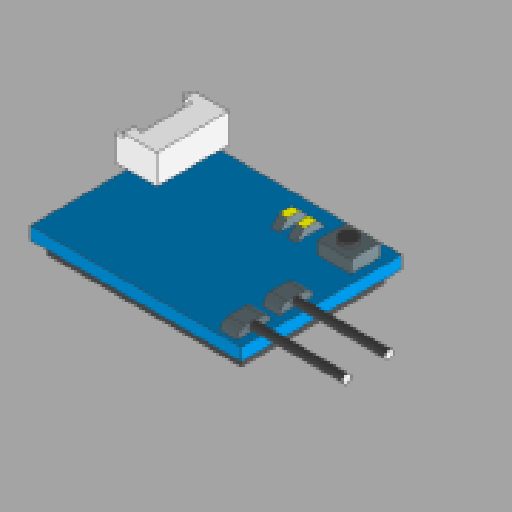
# Autodesk Inventor part: FrSky_XSR_receiver
Saved by Autodesk Inventor 2025 (Build 290162000, 162)
## iProperties
Created: 2024-11-10
Part Number: FrSky_XSR_receiver
Material: 일반
Document SubType Name: Modeling
Designer: OSB
Density: 1 g/cm^3
Appearance: 기본값
Author: OSB
Autodesk Inventor part; units mm, degrees
ref_plane "YZ Plane" through (0, 0, 0) normal (1, 0, 0) x (0, 1, 0)
ref_plane "XZ Plane" through (0, 0, 0) normal (0, 1, 0) x (-1, 0, 0)
ref_plane "XY Plane" through (0, 0, 0) normal (0, 0, 1) x (1, 0, 0)
sketch "스케치1" plane through (0, 0, 0) normal (0, 0, 1) x (1, 0, 0)
  line L0 (0, 0) -> (-19, 0)
  line L1 (-19, 0) -> (-19, 25)
  line L2 (-19, 25) -> (0, 25)
  line L3 (0, 25) -> (0, 0)
  line L4 (-11.5, 3.5) -> (-20, 3.5)
  line L5 (-20, 3.5) -> (-20, -1.5)
  line L6 (-20, -1.5) -> (-11.5, -1.5)
  line L7 (-11.5, -1.5) -> (-11.5, 3.5)
  line L8 (-2, 22) -> (-2, 35) construction
  line L9 (-3, 22) -> (-3, 35) construction
  line L10 (-7, 22) -> (-7, 35) construction
  line L11 (-8, 22) -> (-8, 35) construction
  line L12 (-17.5, 14) -> (-14, 14) construction
  line L13 (-14, 14) -> (-14, 18) construction
  line L14 (-14, 18) -> (-17.5, 18) construction
  line L15 (-17.5, 18) -> (-17.5, 14) construction
  line L16 (-17.5, 20) -> (-14, 20)
  line L17 (-14, 20) -> (-14, 24)
  line L18 (-14, 24) -> (-17.5, 24)
  line L19 (-17.5, 24) -> (-17.5, 20)
  line L20 (-9.5, 22) -> (-5.5, 22)
  line L21 (-5.5, 22) -> (-5.5, 24)
  line L22 (-5.5, 24) -> (-9.5, 24)
  line L23 (-9.5, 24) -> (-9.5, 22)
  line L24 (-4.5, 22) -> (-0.5, 22)
  line L25 (-0.5, 22) -> (-0.5, 24)
  line L26 (-0.5, 24) -> (-4.5, 24)
  line L27 (-4.5, 24) -> (-4.5, 22)
  line L28 (-18, 1) -> (-1, 1)
  line L29 (-1, 1) -> (-1, 24)
  line L30 (-1, 24) -> (-18, 24)
  line L31 (-18, 24) -> (-18, 1)
  line L32 (-17.5, 14.5) -> (-14, 14.5)
  line L33 (-14, 14.5) -> (-14, 15.5)
  line L34 (-14, 15.5) -> (-17.5, 15.5)
  line L35 (-17.5, 15.5) -> (-17.5, 14.5)
  line L36 (-17.5, 16.5) -> (-14, 16.5)
  line L37 (-14, 16.5) -> (-14, 17.5)
  line L38 (-14, 17.5) -> (-17.5, 17.5)
  line L39 (-17.5, 17.5) -> (-17.5, 16.5)
  point P0 (-2.5, 24)
  point P1 (-7.5, 24)
  point P2 (-1, 22)
  dimension "d0" = 19
  dimension "d1" = 25
  dimension "d2" = 11.5
  dimension "d3" = 8.5
  dimension "d4" = 5
  dimension "d5" = 1.5
  dimension "d6" = 2
  dimension "d8" = 1
  dimension "d9" = 7
  dimension "d10" = 1
  dimension "d11" = 7
  dimension "d12" = 4
  dimension "d13" = 3.5
  dimension "d14" = 1.5
  dimension "d15" = 3.5
  dimension "d16" = 1.5
  dimension "d17" = 4
  dimension "d18" = 1
  dimension "d20" = 3
  dimension "d21" = 2
  dimension "d22" = 4
  dimension "d23" = 4
  dimension "d24" = 0.5
  dimension "d25" = 0.5
  dimension "d26" = 10
  dimension "d29" = 1
  dimension "d32" = 1
  dimension "d33" = 1
  dimension "d34" = 1
  dimension "d35" = 0.5
  constraints: 80 end point, 18 parallel, 9 perpendicular, 8 horizontal, 8 point on line, 5 horizontal alignment, 4 vertical, 2 midpoint, 3 other
  measures "d0" distance of L1.end L2.end
  measures "d1" distance of L0.end L1.end
  measures "d2" distance between parallel lines of L3 L7
  measures "d3" distance of L5.end L6.end
  measures "d4" distance of L4.end L5.end
  measures "d5" distance between parallel lines of L6 L0
  measures "d6" distance between parallel lines of L3 L8
  measures "d8" distance between parallel lines of L8 L9
  measures "d9" distance between parallel lines of L10 L3
  measures "d10" distance between parallel lines of L11 L10
  measures "d11" distance between parallel lines of L2 L14
  measures "d12" distance between parallel lines of L14 L12
  measures "d13" distance between parallel lines of L13 L15
  measures "d14" distance between parallel lines of L1 L15
  measures "d15" distance of L17.end L18.end
  measures "d16" distance between parallel lines of L1 L19
  measures "d17" distance of L18.end L16.start
  measures "d18" distance between parallel lines of L2 L18
  measures "d20" distance between parallel lines of L2 L24
  measures "d21" distance of L24.end L25.end
  measures "d22" distance of L20.start L20.end
  measures "d23" distance of L24.start L24.end
  measures "d24" distance from line of point (-2.5, 24) L8
  measures "d25" distance from line of point (-7.5, 24) L10
  measures "d26" distance from line of L8.end L2
  measures "d29" distance between parallel lines of L0 L28
  measures "d32" distance of L32.end L33.end
  measures "d33" distance of L36.end L37.end
  measures "d34" distance between parallel lines of L34 L36
  measures "d35" distance between parallel lines of L12 L32
extrude "돌출1" add sketch "스케치1" along normal blind 1.5 contours L0 L7 L28 L29 L24 L25 L26 L30 L22 L18 L31 L4 L1 L2 L3 | L0 L1 L4 L31 L28 L7 | L28 L31 L4 L7 | L7 L4 L31 L30 L19 L16 L17 L23 L20 L21 L27 L24 L29 L28 | L29 L26 L25 L24 | L24 L27 L26 L29 | L18 L17 L16 L19 | L21 L20 L23 L22 | L35 L34 L33 L32 | L39 L38 L37 L36
extrude "돌출2" add sketch "스케치1" against normal blind 1.5 contours L28 L31 L4 L7 | L7 L4 L31 L30 L19 L16 L17 L23 L20 L21 L27 L24 L29 L28 | L24 L27 L26 L29 | L18 L17 L16 L19 | L21 L20 L23 L22 | L35 L34 L33 L32 | L39 L38 L37 L36
extrude "돌출3" add sketch "스케치1" along normal blind 1 from surface at 1.5 contours L29 L26 L25 L24 | L24 L27 L26 L29 | L21 L20 L23 L22 | L35 L34 L33 L32 | L39 L38 L37 L36
extrude "돌출4" add sketch "스케치1" along normal blind 2 from surface at 1.5 contours L18 L17 L16 L19
extrude "돌출5" add sketch "스케치1" along normal blind 3.5 from surface at 1.5 contours L7 L6 L5 L4 L1 L0 | L0 L1 L4 L31 L28 L7 | L28 L31 L4 L7
sketch "스케치2" plane through (-17.5, 20, 3.5) normal (0, 0, 1) x (1, 0, 0)
  line L0 (3.5, 0) -> (0, 0) projected
  line L1 (3.5, 4) -> (3.5, 0) projected
  line L2 (0, 4) -> (3.5, 4) projected
  line L3 (0, 0) -> (0, 4) projected
  circle A0 centre (1.75, 2) radius 1
  point P0 (17.5, -20)
  point P1 (0, 2)
  point P2 (1.75, 4)
  dimension "d42" = 2
  constraints: 2 midpoint, 1 centre point, 1 horizontal alignment, 1 vertical alignment
  measures "d42" diameter of A0
extrude "돌출6" cut sketch "스케치2" against normal blind 0.5
chamfer "모따기1" distance 1 angle 45 4 edges at (-14, 17, 2.5) (-14, 15, 2.5) (-17.5, 15, 2.5) (-17.5, 17, 2.5)
fillet "모깎기1" radius 1 4 edges at (-9.5, 23, 2.5) (-5.5, 23, 2.5) (-4.5, 23, 2.5) (-0.5, 23, 2.5)
sketch "스케치3" plane through (-4.5, 24, 1.5) normal (0, 1, 0) x (1, 0, 0)
  line L0 (-4, -1) -> (-2, -1) projected
  line L1 (1, -1) -> (3, -1) projected
  circle A0 centre (2, -0.5) radius 0.5
  circle A1 centre (-3, -0.5) radius 0.5
  point P0 (4.5, 1.5)
  point P1 (2, -1)
  point P2 (-3, -1)
  dimension "d49" = 1
  dimension "d50" = 1
  constraints: 2 centre point, 2 midpoint, 2 tangent, 2 vertical alignment
  measures "d49" diameter of A0
  measures "d50" diameter of A1
extrude "돌출7" add sketch "스케치3" along normal blind 11
sketch "스케치4" plane through (-20, -1.5, 5) normal (0, -1, 0) x (1, 0, 0)
  line L0 (8.5, 0) -> (0, 0) projected
  line L1 (0, -3.5) -> (0, 0) projected
  line L2 (8.5, -3.5) -> (0, -3.5) projected
  line L3 (8.5, 0) -> (8.5, -3.5) projected
  line L4 (0.5, -0.5) -> (8, -0.5)
  line L5 (8, -0.5) -> (8, -3)
  line L6 (8, -3) -> (0.5, -3)
  line L7 (0.5, -3) -> (0.5, -0.5)
  line L8 (1, -2.5) -> (1.5, -2.5)
  line L9 (1.5, -2.5) -> (1.5, -2)
  line L10 (1.5, -2) -> (1, -2)
  line L11 (1, -2) -> (1, -2.5)
  line L12 (2.5, -2.5) -> (3, -2.5)
  line L13 (3, -2.5) -> (3, -2)
  line L14 (3, -2) -> (2.5, -2)
  line L15 (2.5, -2) -> (2.5, -2.5)
  line L16 (4, -2.5) -> (4.5, -2.5)
  line L17 (4.5, -2.5) -> (4.5, -2)
  line L18 (4.5, -2) -> (4, -2)
  line L19 (4, -2) -> (4, -2.5)
  line L20 (5.5, -2.5) -> (6, -2.5)
  line L21 (6, -2.5) -> (6, -2)
  line L22 (6, -2) -> (5.5, -2)
  line L23 (5.5, -2) -> (5.5, -2.5)
  line L24 (7, -2.5) -> (7.5, -2.5)
  line L25 (7.5, -2.5) -> (7.5, -2)
  line L26 (7.5, -2) -> (7, -2)
  line L27 (7, -2) -> (7, -2.5)
  point P0 (20, -5)
  point P1 (4.25, -2)
  point P2 (4.25, -0.5)
  dimension "d53" = 0.5
  dimension "d54" = 0.5
  dimension "d55" = 0.5
  dimension "d58" = 1.5
  dimension "d64" = 0.5
  constraints: 48 end point, 2 horizontal, 2 midpoint, 2 parallel, 1 perpendicular, 1 vertical alignment, 35 other
  measures "d53" distance between parallel lines of L0 L4
  measures "d54" distance of L10.end L8.start
  measures "d55" distance of L8.start L8.end
  measures "d58" distance of L8.start L12.start
  measures "d64" distance between parallel lines of L6 L8
extrude "돌출8" cut sketch "스케치4" against normal blind 4.5 contours L4 L5 L6 L7
sketch "스케치5" plane through (-20, -1.5, 5) normal (0, 0, 1) x (1, 0, 0)
  line L0 (8.5, 0) -> (0, 0) projected
  line L1 (8.5, 5) -> (8.5, 0) projected
  line L2 (0, 5) -> (8.5, 5) projected
  line L3 (0, 0) -> (0, 5) projected
  line L4 (7.25, 2) -> (1.25, 2)
  line L5 (1.25, 2) -> (1.25, 1)
  line L6 (1.25, 1) -> (0, 1)
  line L7 (7.25, 2) -> (7.25, 1)
  line L8 (7.25, 1) -> (8.5, 1)
  line L9 (8, 0) -> (8, 4.5) projected
  line L10 (0.5, 0) -> (0.5, 4.5) projected
  line L11 (8.5, 5) -> (8.5, 0) projected
  line L12 (0, 0) -> (0, 5) projected
  point P0 (4.25, 2)
  point P1 (4.25, 0)
  point P2 (0, 1)
  point P3 (8.5, 1)
  dimension "d67" = 2
  dimension "d68" = 1
  dimension "d69" = 6
  constraints: 10 end point, 2 horizontal, 2 midpoint, 2 perpendicular, 2 point on line, 1 horizontal alignment, 1 vertical, 1 vertical alignment
  measures "d67" distance between parallel lines of L0 L4
  measures "d68" distance between parallel lines of L6 L0
  measures "d69" distance of L4.start L4.end
extrude "돌출9" cut sketch "스케치5" against normal blind 0.5 contours L0 L9 L8 L1 | L0 L10 L6 L5 L4 L7 L8 L9 | L0 L3 L6 L10
equation "\"d10\" = d8"
equation "\"d24\" = 0.5 * d8"
equation "\"d25\" = 0.5 * d10"
equation "\"d33\" = d32"
equation "\"d68\" = 0.5 * d67"
